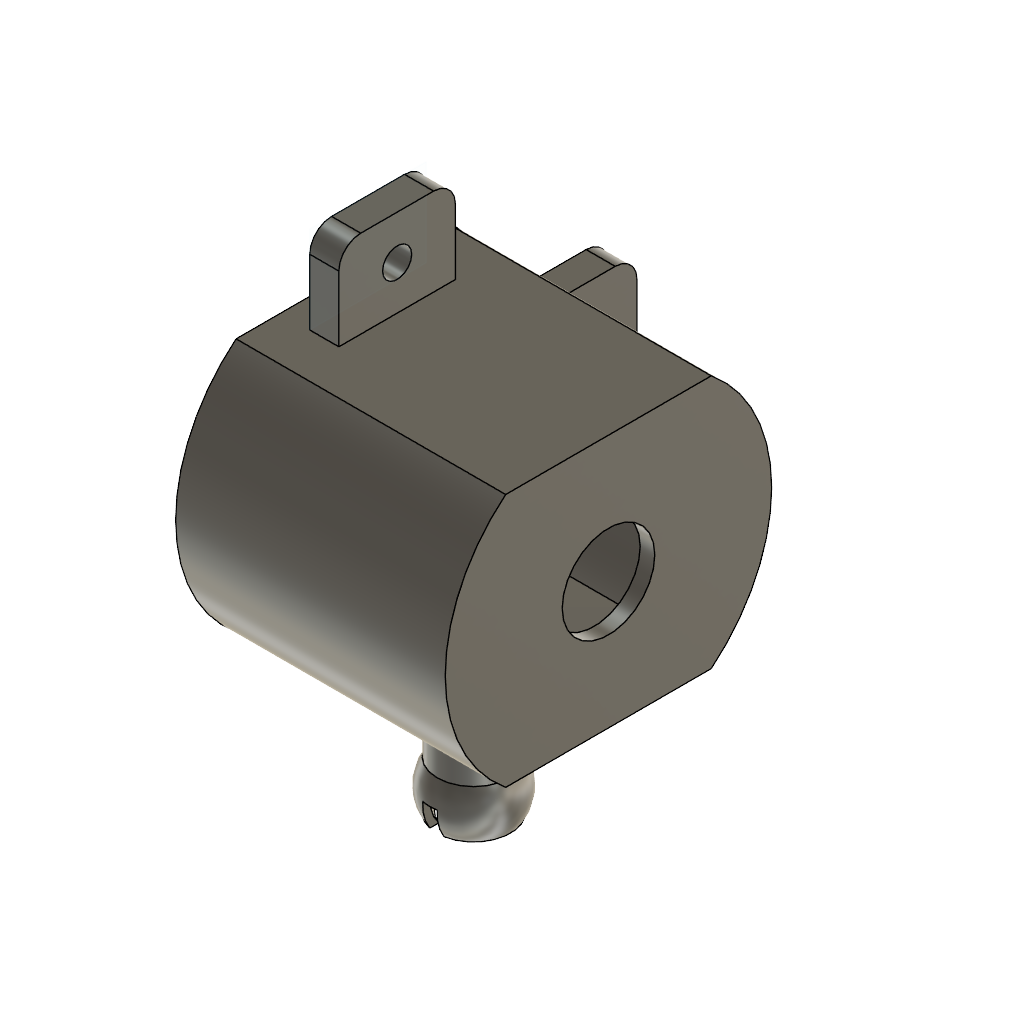
motorhalterung balljoint (Autodesk Fusion 360 design; units mm, degrees)
part number: 2026-11-07-18-57-53-680
Autodesk Fusion 360 part; units mm, degrees
sketch "Skizze1" plane through (0, 0, 0) normal (0, 0, 1) x (1, 0, 0)
  line L0 (0, 0) -> (26, 0)
  line L1 (26, 0) -> (26, 21)
  line L2 (26, 21) -> (0, 21)
  line L3 (0, 21) -> (0, 0)
  dimension "d1" = 21
  constraint coincident L0.start L3.end
  constraint horizontal L0
  constraint perpendicular L0 L1
  constraint perpendicular L1 L2
  constraint perpendicular L2 L3
  measures "d1" distance of L0.end L1.end
sketch "Skizze2" plane through (0, 0, 0) normal (0, 0, 1) x (1, 0, 0)
sketch "Skizze3" plane through (0, 0, 0) normal (1, 0, 0) x (0, 1, 0)
sketch "Skizze4" plane through (0, 0, 0) normal (1, 0, 0) x (0, 1, 0)
sketch "Skizze5" plane through (0, 0, 0) normal (1, 0, 0) x (0, 1, 0)
  line L0 (-6.6895, 0) -> (-6.6895, 7.7)
  line L1 (-6.6895, 0) -> (-6.6895, -7.7)
  line L2 (-6.6895, 7.7) -> (6.6895, 7.7)
  line L3 (-6.6895, -7.7) -> (6.6895, -7.7)
  line L4 (6.6895, 7.7) -> (6.6895, -7.7)
  arc A0 (-6.6895, 7.7) -> (-6.6895, -7.7) centre (0, 0) ccw
  arc A1 (6.6895, -7.7) -> (6.6895, 7.7) centre (0, 0) ccw
  dimension "d10" = 7.7
  dimension "d11" = 20.4
  constraint vertical L0
  constraint coincident A0.centre A1.centre
  constraint parallel L0 L1
  constraint perpendicular L0 L2
  constraint perpendicular L1 L3
  constraint concentric A0 A1
  measures "d10" distance of L0.start L0.end
  measures "d11" diameter of A0
extrude "Extrusion2" add sketch "Skizze5" along normal blind 17.5 makes body 1
shell "Schale1" thickness 1 outward yes removed faces 1 at (0, -2.914, 2.5667) on bodies 1
hole "Bohrung1" at (18.5, 0, 0) direction (-1, 0, 0) diameter 6.35 depth 5 tip angle 118 bodies 1
sketch "Skizze6" plane through (0, 0, 8.7) normal (0, 0, 1) x (-1, 0, 0)
  line L0 (0, -7.0533) -> (0, 7.0533)
  line L1 (0, 7.0533) -> (-18.5, 7.0533)
  line L2 (-18.5, 7.0533) -> (-18.5, -7.0533)
  line L3 (-18.5, -7.0533) -> (0, -7.0533)
  line L4 (-2, -4) -> (-4, -4)
  line L5 (-4, -4) -> (-4, 4)
  line L6 (-4, 4) -> (-2, 4)
  line L7 (-2, 4) -> (-2, -4)
  constraint horizontal L4
  constraint vertical L5
  constraint horizontal L6
  constraint vertical L7
extrude "Extrusion3" add sketch "Skizze6" along normal blind 6 contours L4 L5 L6 L7 bodies 1
sketch "Skizze7" plane through (2, 0, 0) normal (-1, 0, 0) x (0, -1, 0)
  line L0 (-4, 8.7) -> (4, 8.7)
  line L1 (4, 8.7) -> (4, 14.7)
  line L2 (4, 14.7) -> (-4, 14.7)
  line L3 (-4, 14.7) -> (-4, 8.7)
hole "Bohrung2" at (2, 0, 11.7001) direction (1, 0, 0) diameter 2 depth 5 tip angle 118 bodies 1
fillet "Abrundung1" radius 1.5 1 edges at (3, 4, 14.7) on bodies 1
fillet "Abrundung2" radius 1.5 1 edges at (3, -4, 14.7) on bodies 1
sketch "Skizze8" plane through (0, 0, 0) normal (0, 1, 0) x (1, 0, 0)
sketch "Skizze9" plane through (0, 0, 0) normal (1, 0, 0) x (0, 1, 0)
  line L0 (10.46, 4, 2) -> (16.46, 4, 2)
  line L1 (16.46, 4, 2) -> (16.46, -4, 2)
  line L2 (16.46, -4, 2) -> (10.46, -4, 2)
  line L3 (10.46, 4, 2) -> (10.46, -4, 2)
  dimension "d27" = 8
  dimension "d28" = 6
extrude "Extrusion4" add sketch "Skizze9" along normal blind 2 contours L0 L1 L2 L3 in plane through (2, 0, 0) normal (1, 0, 0) bodies 1
fillet "Abrundung3" radius 1.5 1 edges at (3, 16.46, 4) on bodies 1
fillet "Abrundung4" radius 1.5 1 edges at (3, 16.46, -4) on bodies 1
sketch "Skizze10" plane through (0, 0, -8.7) normal (0, 0, -1) x (1, 0, 0)
  line L0 (0, 7.0533) -> (0, -7.0533)
  line L1 (0, -7.0533) -> (18.5, -7.0533)
  line L2 (18.5, -7.0533) -> (18.5, 7.0533)
  line L3 (18.5, 7.0533) -> (0, 7.0533)
  circle A0 centre (9.25, 0) radius 2.5
  dimension "d36" = 5
  measures "d36" diameter of A0
extrude "Extrusion5" add sketch "Skizze10" along normal blind 8 contours A0 bodies 1
sketch "Skizze11" plane through (0, 0, -16.7) normal (0, 0, -1) x (1, 0, 0)
  circle A0 centre (9.25, 0) radius 2.5
sketch "Skizze12" plane through (0, 0, 0) normal (1, 0, 0) x (0, 1, 0)
  circle A0 through (-2.5, -16.7, 9.25) (1.25, -16.7, 11.4151) (1.25, -16.7, 7.0849)
  line L0 (0, -18.3209, 9.25) -> (0, -13.7, 9.25)
  line L1 (-2.5245, -18.3209, 9.25) -> (2.5245, -18.3209, 9.25)
  arc A1 through (2.5245, -18.3209, 9.25) (0, -13.7, 9.25) (-2.5245, -18.3209, 9.25)
  arc A2 through (1.9034, -18.3209, 9.25) (0, -14.2, 9.25) (-1.9034, -18.3209, 9.25)
  dimension "d39" = 6
  dimension "d41" = 5
revolve "Drehen1" cut sketch "Skizze12" angle 360 about axis through (9.25, 0, -18.3209) along (0, 0, 1) contours L0 L1 A2 in plane through (9.25, 0, 0) normal (1, 0, 0) picked at (9.25, 0.1182, -15.5821) bodies 1
revolve "Drehen2" cut sketch "Skizze12" angle 360 about axis through (9.25, 0, -18.3209) along (0, 0, 1) contours L0 L1 A1 A2 in plane through (9.25, 0, 0) normal (1, 0, 0) picked at (9.25, 2.4559, -18.1002) bodies 1
revolve "Drehen3" add sketch "Skizze12" angle 360 about axis through (9.25, 0, -8.7) along (0, 0, 1) contours L0 L1 A1 A2 in plane through (9.25, 0, 0) normal (1, 0, 0) picked at (9.25, -2.4559, -18.1002) bodies 1
box "Grundkörper Quader1" add length 8 width 2 height 1 placed x (0, 1, 0) y (-1, 0, 0) z (0, 0, 1) at (1, 25, 0) separate body makes body 2
move_body "Verschieben1" bodies 2 to x (0, 0, -1) y (0, 1, 0) z (1, 0, 0) at (8.7, -29, -17.5)
combine "Kombinieren1" operation cut target body 1 tool bodies 2
hole "Bohrung3" at (2, 13.6499, 0) direction (1, 0, 0) diameter 2 depth 3 tip angle 118 bodies 1
